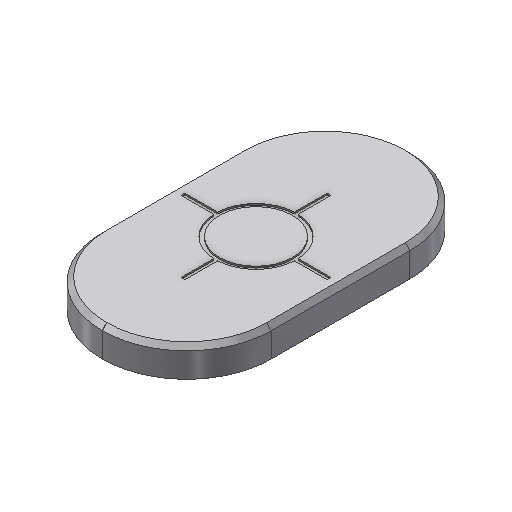
# Autodesk Inventor part: PRT - 9034 - CAMTARSCR - V04
Saved by Autodesk Inventor 2025.5 (Build 295498000, 498)
## iProperties
Created: 2026-11-05
Part Number: PRT - 9034 - CAMTARSCR - V04
Material: Generisch
Description: Screen cap: 0.6 mm printed white screen with a reticle on the inner face, cone-centred, two 8x3 magnets. Print on the screen, white.
Document SubType Name: Modeling
Designer: benir
Density: 1 g/cm^3
Appearance: Smooth - White
Author: benir
Autodesk Inventor part; units mm, degrees
ref_plane "y=cap_back_y" through (0, 12.3, 0) normal (0, 1, 0) x (-1, 0, 0)
sketch "cap sketch" plane through (0, 12.3, 0) normal (0, 1, 0) x (-1, 0, 0)
  line L0 (11, -20) -> (-11, -20)
  line L1 (-11, -20) -> (-11, 20)
  line L2 (-11, 20) -> (11, 20)
  line L3 (11, 20) -> (11, -20)
  line L4 (0, -28) -> (0, 28) projected
  line L5 (15.4, 0) -> (-15.4, 0) projected
  dimension "d3" = 22
  dimension "d4" = 40
  constraints: 8 end point, 2 parallel, 1 horizontal, 1 perpendicular, 2 other
  measures "d3" distance of L0.start L0.end
  measures "d4" distance of L2.end L0.start
extrude "cap" add sketch "cap sketch" along normal blind 3.8
fillet "round ends" radius 10.98 4 edges at (11, 14.2, -20) (11, 14.2, 20) (-11, 14.2, 20) (-11, 14.2, -20)
sketch "ring sketch" plane through (0, 12.3, 0) normal (0, 1, 0) x (-1, 0, 0)
  circle A0 centre (0, 0) radius 10.6
  dimension "d8" = 21.2
  constraints: 1 centre point
  measures "d8" diameter of A0
extrude "centring ring" add sketch "ring sketch" against normal blind 0.6 draft -45
ref_plane "y=ring_tip_y - 1 mm" through (0, 10.7, 0) normal (0, 1, 0) x (-1, 0, 0)
sketch "cap bore sketch" plane through (0, 10.7, 0) normal (0, 1, 0) x (-1, 0, 0)
  circle A0 centre (0, 0) radius 9.2
  dimension "d12" = 18.4
  constraints: 1 centre point
  measures "d12" diameter of A0
extrude "bore up to the screen" cut sketch "cap bore sketch" along normal blind 4.8
sketch "cap magnet sketch" plane through (0, 12.3, 0) normal (0, 1, 0) x (-1, 0, 0)
  circle A0 centre (0, 15.5) radius 4.1
  line L0 (0, -28) -> (0, 28) projected
  circle A1 centre (0, -15.5) radius 4.1
  point P0 (0, 0)
  dimension "d15" = 15.5
  dimension "d16" = 8.2
  dimension "d17" = 15.5
  dimension "d18" = 8.2
  constraints: 2 centre point, 2 point on line
  measures "d15" distance of point (0, 0) A0.centre
  measures "d16" diameter of A0
  measures "d17" distance of point (0, 0) A1.centre
  measures "d18" diameter of A1
extrude "magnet pockets" cut sketch "cap magnet sketch" along normal blind 3.4
chamfer "front edge" distance 0.6 angle 45 8 edges at (-7.784, 16.1, -16.784) (0, 16.1, -20) (-11, 16.1, 0) (-7.784, 16.1, 16.784) (0, 16.1, 20) (7.784, 16.1, 16.784) (11, 16.1, 0) (7.784, 16.1, -16.784)
ref_plane "y=screen_out_y" through (0, 16.1, 0) normal (0, 1, 0) x (-1, 0, 0)
sketch "target sketch" plane through (0, 16.1, 0) normal (0, 1, 0) x (-1, 0, 0)
  line L0 (-5, -0.25) -> (-9.5, -0.25)
  line L1 (-9.5, -0.25) -> (-9.5, 0.25)
  line L2 (-9.5, 0.25) -> (-5, 0.25)
  line L3 (-5, 0.25) -> (-5, -0.25)
  line L4 (15.4, 0) -> (-15.4, 0) projected
  line L5 (9.5, -0.25) -> (5, -0.25)
  line L6 (5, -0.25) -> (5, 0.25)
  line L7 (5, 0.25) -> (9.5, 0.25)
  line L8 (9.5, 0.25) -> (9.5, -0.25)
  line L9 (0.25, 5) -> (-0.25, 5)
  line L10 (-0.25, 5) -> (-0.25, 9.5)
  line L11 (-0.25, 9.5) -> (0.25, 9.5)
  line L12 (0.25, 9.5) -> (0.25, 5)
  line L13 (0, -28) -> (0, 28) projected
  line L14 (0.25, -9.5) -> (-0.25, -9.5)
  line L15 (-0.25, -9.5) -> (-0.25, -5)
  line L16 (-0.25, -5) -> (0.25, -5)
  line L17 (0.25, -5) -> (0.25, -9.5)
  point P0 (0, 0)
  dimension "d25" = 0.5
  dimension "d26" = 5
  dimension "d27" = 9.5
  dimension "d28" = 0.5
  dimension "d29" = 9.5
  dimension "d30" = 5
  dimension "d31" = 0.5
  dimension "d32" = 5
  dimension "d33" = 9.5
  dimension "d34" = 0.5
  dimension "d35" = 9.5
  dimension "d36" = 5
  constraints: 32 end point, 8 parallel, 4 horizontal, 4 perpendicular, 4 other
  measures "d25" distance of L2.end L0.start
  measures "d26" horizontal distance of point (0, 0) L2.end
  measures "d27" horizontal distance of point (0, 0) L0.end
  measures "d28" distance of L7.end L5.start
  measures "d29" horizontal distance of point (0, 0) L7.end
  measures "d30" horizontal distance of point (0, 0) L5.end
  measures "d31" distance of L9.start L9.end
  measures "d32" vertical distance of point (0, 0) L9.start
  measures "d33" vertical distance of point (0, 0) L10.end
  measures "d34" distance of L14.start L14.end
  measures "d35" vertical distance of point (0, 0) L14.start
  measures "d36" vertical distance of point (0, 0) L15.end
extrude "target: crosshair for the eye" cut sketch "target sketch" against normal blind 0.2
sketch "target ring sketch" plane through (0, 16.1, 0) normal (0, 1, 0) x (-1, 0, 0)
  circle A0 centre (0, 0) radius 5.25
  circle A1 centre (0, 0) radius 4.75
  dimension "d39" = 10.5
  dimension "d40" = 9.5
  constraints: 2 centre point
  measures "d39" diameter of A0
  measures "d40" diameter of A1
extrude "target: ring" cut sketch "target ring sketch" against normal blind 0.2
ref_plane "y=screen_in_y" through (0, 15.5, 0) normal (0, 1, 0) x (-1, 0, 0)
sketch "reticle sketch" plane through (0, 15.5, 0) normal (0, 1, 0) x (-1, 0, 0)
  line L0 (-1.5, -0.225) -> (-8, -0.225)
  line L1 (-8, -0.225) -> (-8, 0.225)
  line L2 (-8, 0.225) -> (-1.5, 0.225)
  line L3 (-1.5, 0.225) -> (-1.5, -0.225)
  line L4 (15.4, 0) -> (-15.4, 0) projected
  line L5 (8, -0.225) -> (1.5, -0.225)
  line L6 (1.5, -0.225) -> (1.5, 0.225)
  line L7 (1.5, 0.225) -> (8, 0.225)
  line L8 (8, 0.225) -> (8, -0.225)
  line L9 (0.225, 1.5) -> (-0.225, 1.5)
  line L10 (-0.225, 1.5) -> (-0.225, 8)
  line L11 (-0.225, 8) -> (0.225, 8)
  line L12 (0.225, 8) -> (0.225, 1.5)
  line L13 (0, -28) -> (0, 28) projected
  line L14 (0.225, -8) -> (-0.225, -8)
  line L15 (-0.225, -8) -> (-0.225, -1.5)
  line L16 (-0.225, -1.5) -> (0.225, -1.5)
  line L17 (0.225, -1.5) -> (0.225, -8)
  point P0 (0, 0)
  dimension "d44" = 0.45
  dimension "d45" = 1.5
  dimension "d46" = 8
  dimension "d47" = 0.45
  dimension "d48" = 8
  dimension "d49" = 1.5
  dimension "d50" = 0.45
  dimension "d51" = 1.5
  dimension "d52" = 8
  dimension "d53" = 0.45
  dimension "d54" = 8
  dimension "d55" = 1.5
  constraints: 32 end point, 8 parallel, 4 horizontal, 4 perpendicular, 4 other
  measures "d44" distance of L2.end L0.start
  measures "d45" horizontal distance of point (0, 0) L2.end
  measures "d46" horizontal distance of point (0, 0) L0.end
  measures "d47" distance of L7.end L5.start
  measures "d48" horizontal distance of point (0, 0) L7.end
  measures "d49" horizontal distance of point (0, 0) L5.end
  measures "d50" distance of L9.start L9.end
  measures "d51" vertical distance of point (0, 0) L9.start
  measures "d52" vertical distance of point (0, 0) L10.end
  measures "d53" distance of L14.start L14.end
  measures "d54" vertical distance of point (0, 0) L14.start
  measures "d55" vertical distance of point (0, 0) L15.end
extrude "reticle ribs (open at the centre)" add sketch "reticle sketch" against normal blind 0.35
sketch "tick sketch" plane through (0, 15.5, 0) normal (0, 1, 0) x (-1, 0, 0)
  line L0 (-4.775, -1.6) -> (-5.225, -1.6)
  line L1 (-5.225, -1.6) -> (-5.225, 1.6)
  line L2 (-5.225, 1.6) -> (-4.775, 1.6)
  line L3 (-4.775, 1.6) -> (-4.775, -1.6)
  line L4 (15.4, 0) -> (-15.4, 0) projected
  line L5 (1.6, 4.775) -> (-1.6, 4.775)
  line L6 (-1.6, 4.775) -> (-1.6, 5.225)
  line L7 (-1.6, 5.225) -> (1.6, 5.225)
  line L8 (1.6, 5.225) -> (1.6, 4.775)
  line L9 (0, -28) -> (0, 28) projected
  line L10 (5.225, -1.6) -> (4.775, -1.6)
  line L11 (4.775, -1.6) -> (4.775, 1.6)
  line L12 (4.775, 1.6) -> (5.225, 1.6)
  line L13 (5.225, 1.6) -> (5.225, -1.6)
  line L14 (1.6, -5.225) -> (-1.6, -5.225)
  line L15 (-1.6, -5.225) -> (-1.6, -4.775)
  line L16 (-1.6, -4.775) -> (1.6, -4.775)
  line L17 (1.6, -4.775) -> (1.6, -5.225)
  line L18 (-0.8, 6.8) -> (-2.4, 6.8)
  line L19 (-2.4, 6.8) -> (-2.4, 7.25)
  line L20 (-2.4, 7.25) -> (-0.8, 7.25)
  line L21 (-0.8, 7.25) -> (-0.8, 6.8)
  point P0 (0, 0)
  dimension "d37" = 0.2
  dimension "d58" = 3.2
  dimension "d59" = 4.775
  dimension "d60" = 5.225
  dimension "d61" = 3.2
  dimension "d62" = 4.775
  dimension "d63" = 5.225
  dimension "d64" = 3.2
  dimension "d65" = 4.775
  dimension "d66" = 5.225
  dimension "d67" = 3.2
  dimension "d68" = 4.775
  dimension "d69" = 5.225
  dimension "d70" = 0.8
  dimension "d71" = 2.4
  dimension "d72" = 6.8
  dimension "d73" = 7.25
  constraints: 40 end point, 10 parallel, 5 horizontal, 5 perpendicular, 4 other
  measures "d58" distance of L2.end L0.start
  measures "d59" horizontal distance of point (0, 0) L2.end
  measures "d60" horizontal distance of point (0, 0) L0.end
  measures "d61" distance of L5.start L5.end
  measures "d62" vertical distance of point (0, 0) L5.start
  measures "d63" vertical distance of point (0, 0) L6.end
  measures "d64" distance of L10.end L11.end
  measures "d65" horizontal distance of point (0, 0) L10.end
  measures "d66" horizontal distance of point (0, 0) L12.end
  measures "d67" distance of L15.end L16.end
  measures "d68" vertical distance of point (0, 0) L15.end
  measures "d69" vertical distance of point (0, 0) L14.start
  measures "d70" horizontal distance of point (0, 0) L20.end
  measures "d71" horizontal distance of point (0, 0) L18.end
  measures "d72" vertical distance of point (0, 0) L18.start
  measures "d73" vertical distance of point (0, 0) L19.end
extrude "ticks at +-tick_r and the mark for up" add sketch "tick sketch" against normal blind 0.35
equation "\"d3\" = 2 * cap_w"
equation "\"d4\" = 2 * cap_h"
equation "\"d5\" = cap_t"
equation "\"d8\" = ring_d0"
equation "\"d9\" = ring_h"
equation "\"d10\" = -cone_ang"
equation "\"d12\" = cap_bore_d"
equation "\"d15\" = mag_z"
equation "\"d16\" = mag_pocket_d"
equation "\"d17\" = mag_z"
equation "\"d18\" = mag_pocket_d"
equation "\"d19\" = mag_pocket_h"
equation "\"d21\" = cap_edge"
equation "\"d22\" = cap_edge"
equation "\"d25\" = groove_w"
equation "\"d26\" = groove_r"
equation "\"d28\" = groove_w"
equation "\"d30\" = groove_r"
equation "\"d31\" = groove_w"
equation "\"d32\" = groove_r"
equation "\"d34\" = groove_w"
equation "\"d36\" = groove_r"
equation "\"d37\" = groove_h"
equation "\"d39\" = groove_d1"
equation "\"d40\" = groove_d0"
equation "\"d41\" = groove_h"
equation "\"d44\" = rib_w"
equation "\"d45\" = rib_r0"
equation "\"d46\" = rib_r1"
equation "\"d47\" = rib_w"
equation "\"d48\" = rib_r1"
equation "\"d49\" = rib_r0"
equation "\"d50\" = rib_w"
equation "\"d51\" = rib_r0"
equation "\"d52\" = rib_r1"
equation "\"d53\" = rib_w"
equation "\"d54\" = rib_r1"
equation "\"d55\" = rib_r0"
equation "\"d56\" = rib_h"
equation "\"d58\" = 2 * tick_l"
equation "\"d59\" = tick_r - 0.5 * rib_w"
equation "\"d60\" = tick_r + 0.5 * rib_w"
equation "\"d61\" = 2 * tick_l"
equation "\"d62\" = tick_r - 0.5 * rib_w"
equation "\"d63\" = tick_r + 0.5 * rib_w"
equation "\"d64\" = 2 * tick_l"
equation "\"d65\" = tick_r - 0.5 * rib_w"
equation "\"d66\" = tick_r + 0.5 * rib_w"
equation "\"d67\" = 2 * tick_l"
equation "\"d68\" = tick_r - 0.5 * rib_w"
equation "\"d69\" = tick_r + 0.5 * rib_w"
equation "\"d74\" = rib_h"
equation "\"front_y\" = 12.2"
equation "\"cap_gap\" = 0.1"
equation "\"cap_back_y\" = front_y + cap_gap"
equation "\"d2\" = cap_back_y"
equation "\"cap_w\" = 11"
equation "\"sensor_y\" = -4.5"
equation "\"screen_in_y\" = sensor_y + screen_d"
equation "\"scr_t\" = 0.6"
equation "\"screen_out_y\" = screen_in_y + scr_t"
equation "\"cap_t\" = screen_out_y - cap_back_y"
equation "\"seat_c\" = 0.5"
equation "\"seat_r\" = 0.5 * bore_d + seat_c"
equation "\"ring_r0\" = seat_r + cap_gap"
equation "\"ring_d0\" = 2 * ring_r0"
equation "\"ring_h\" = 0.6"
equation "\"cone_ang\" = 45deg"
equation "\"ring_tip_y\" = cap_back_y - ring_h"
equation "\"cap_bore_d\" = 18.4"
equation "\"mag_z\" = 15.5"
equation "\"mag_d\" = 8"
equation "\"mag_fit\" = 0.2"
equation "\"mag_pocket_d\" = mag_d + mag_fit"
equation "\"mag_t\" = 3"
equation "\"mag_sink\" = 0.4"
equation "\"mag_pocket_h\" = mag_t + mag_sink"
equation "\"cap_edge\" = 0.6"
equation "\"d24\" = screen_out_y"
equation "\"groove_r\" = 5"
equation "\"groove_w\" = 0.5"
equation "\"rib_r1\" = 8"
equation "\"groove_h\" = 0.2"
equation "\"groove_d1\" = 2 * groove_r + groove_w"
equation "\"groove_d0\" = 2 * groove_r - groove_w"
equation "\"d43\" = screen_in_y"
equation "\"rib_r0\" = 1.5"
equation "\"rib_w\" = 0.45"
equation "\"rib_h\" = 0.35"
equation "\"tick_r\" = 5"
equation "\"tick_l\" = 1.6"
equation "\"cap_h\" = 20"
equation "\"screen_d\" = 20"
equation "\"bore_d\" = 20"
body "Solid2"
